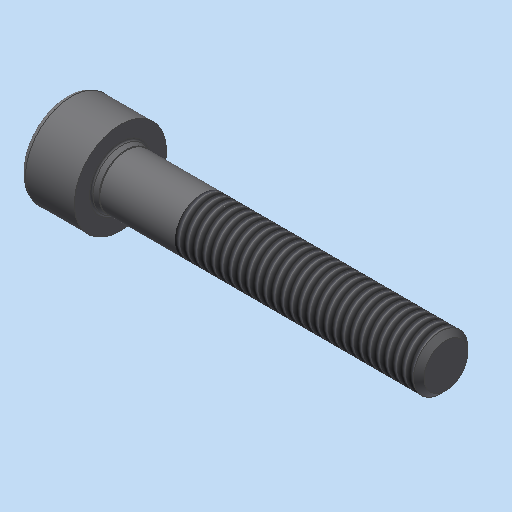
# Autodesk Inventor part: Zylinderschraube_ISO_4762___M5x30
Saved by Autodesk Inventor 2023.3 (Build 273359000, 359)
## iProperties
Shininess: 64.0
Length Units: 11269
Angle Units: 11279
Time Units: 11290
Mass Units: 11283
Length Display Precision: 3
Angle Display Precision: 2
Compacted: True
Part Number: Zylinderschraube_ISO_4762___M5x30
Document SubType Name: Modeling
Created: 2004-04-03
Material: xStahl_AnP_Dummymaterial
Description: =<RBPARTNOTITLE2>
Vendor: NORM8
Designer: S.Riedelsheimer
Manufacturer: Standard
Standards Organization: Custom
Density: 7.85 g/cm^3
Appearance: Stahl - normal AnP
Mass: 6.45697 g
Surface Area: 7.47956 cm^2
Volume: 0.822544 cm^3
DOC_ID: 5 F45 Zylinderschraube_ISO_4762___M5x30
GAIN_REFID: 20__Zylinderschraube_ISO_4762___M5x30:A93E3
Control State: 0
Master: False
Checked Out: False
CNS_NB: Zylinderschraube ISO 4762 - M5x30
CNS_NN: ISO 4762
CNS_NT: Zylinderschrauben mit Innensechskant
CNS_NBSYN: Zylinderschraube ISO 4762 - $NENN.
CNS_LINA: Zylinderschraube ISO 4762 - M5x30
CNS_D: 5.000
CNS_D3: 4.019
CNS_P: 0.800
CNS_L: 30.000
CNS_S: 4.000
CNS_HM: 22.000
CNS_DK: 8.500
CNS_DA: 5.700
CNS_DS: 5.000
CNS_E: 4.580
CNS_K: 5.000
CNS_R: 0.200
CNS_T: 2.500
CNS_V: 0.500
CNS_DW: 8.030
CNS_W: 1.900
CNS_LF: 0.600
CNS_LG: 8.000
CNS_FORM: 0.000
CNS_NENN: M5x30
CNS_KT: DUMMY
PSOL_IDENT_0: {C:\partsolutions8\data\23d-libs\bosch_bamberg\schrauben\zylinderschrauben\din_en_iso_4762.prj},170
PSOL_IDENT_1: {M=Nenngewinde},{VTYP=3D},{NB=Zylinderschraube ISO 4762 - M5x30},{NN=ISO 4762},{DATE=26.11.2003},{GE
PSOL_IDENT_2: OMDATE=26.11.2003},{VERSION=v2},{LINEID=530},{LINESUBID=-1},{WBVAR=}  {NB=Zylinderschraube ISO 4762
PSOL_IDENT_3: - M5x30},{LINA=Zylinderschraube ISO 4762 - M5x30},{KT=DUMMY},{IDNR=},{D=5.000},{D3=4.019},{P=0.800},
PSOL_IDENT_4: {L=30.000},{S=4.000},{HM=22.000},{DK=8.500},{DA=5.700},{DS=5.000},{E=4.580},{K=5.000},{R=0.200},{T=2
PSOL_IDENT_5: .500},{V=0.500},{DW=8.030},{W=1.900},{LF=0.600},{LG=8.000},{FORM=0.000},{NENN=M5x30}
DEF_STKID: T18915
Bezeichnung1: Zylinderschraube ISO 4762 - M5x30
Bezeichnung2: Zylinderschrauben mit Innensechskant
RBPARTNOTITLE2: Zylinderschrauben mit Innensechskant
RBPARTNOTITLE1: Hexagon socket head cap screws
AnP_Kategorie: 4
RBDRAWINGMISSINGSPEC: --
RBPARTMADEOF: ISO 4762 - M5x30 - 8.8 verzinkt
Density: 0.0
Volumn: 0.0
Area: 0.0
PropertySet Name: Model Information
Title: Zylinderschraube ISO 4762 - M5x30
Author: S.Riedelsheimer
Keywords: =<RBPARTMADEOF>
Comments: =<RBSURFACE2>
Revision Number: 01
Autodesk Inventor part; units mm, degrees
sketch "Sketch_1" plane through (0, 0, 0) normal (0, 1, 0) x (-1, 0, 0)
  line L0 (-33, 0) -> (8, 0)
  line L1 (0.7453, 0) -> (1.9, -2)
  line L2 (1.9, -2) -> (4.71, -2)
  line L3 (4.71, -2) -> (5, -2.29)
  line L4 (5, -2.29) -> (5, -3.75)
  arc A0 (4.5, -4.25) -> (5, -3.75) centre (4.5, -3.75) ccw
  line L5 (4.5, -4.25) -> (0, -4.25)
  line L6 (0, -4.25) -> (0, -2.85)
  arc A1 (0, -2.85) -> (-0.1298, -2.6627) centre (-0.2, -2.85) ccw
  line L7 (-0.1298, -2.6627) -> (-0.5298, -2.5127)
  arc A2 (-0.5298, -2.5127) -> (-0.6, -2.5) centre (-0.6, -2.7) ccw
  line L8 (-0.6, -2.5) -> (-29.5095, -2.5)
  line L9 (-29.5095, -2.5) -> (-30, -2.0095)
  line L10 (-30, -2.0095) -> (-30, 0)
  line L11 (-30, 0) -> (0.7453, 0)
  constraints: 24 end point, 6 point on circle, 3 centre point
revolve "Drehung1" add sketch "Sketch_1" angle 360 about axis through (33, 0, 0) along (1, 0, 0)
thread "Gewinde1" size "M5x0.8" class "6g" standard "ANSI Metric M Profile" length 22
sketch "Skizze_1" plane through (-1.9, 0, 0) normal (1, 0, 0) x (0, 0, -1)
  line L0 (-2, 1.1547) -> (-2, -1.1547)
  line L1 (-2, -1.1547) -> (0, -2.3094)
  line L2 (0, -2.3094) -> (2, -1.1547)
  line L3 (2, -1.1547) -> (2, 1.1547)
  line L4 (2, 1.1547) -> (0, 2.3094)
  line L5 (0, 2.3094) -> (-2, 1.1547)
  constraints: 12 end point
extrude "Extrusion1" cut sketch "Skizze_1" against normal blind 5
ref_plane "IP1_XY" through (0, 0, 0) normal (1, 0, 0) x (0, 0, -1)
ref_plane "IP1_YZ" through (0, 0, 0) normal (0, 0, -1) x (0, 1, 0)
ref_plane "IP3_XY" through (30, 0, 0) normal (1, 0, 0) x (0, 0, -1)
ref_plane "IP3_YZ" through (30, 0, 0) normal (0, 0, -1) x (0, 1, 0)
ref_plane "IP2_XY" through (-5, 0, 0) normal (1, 0, 0) x (0, 0, -1)
ref_plane "IP2_YZ" through (-5, 0, 0) normal (0, 0, -1) x (0, 1, 0)
